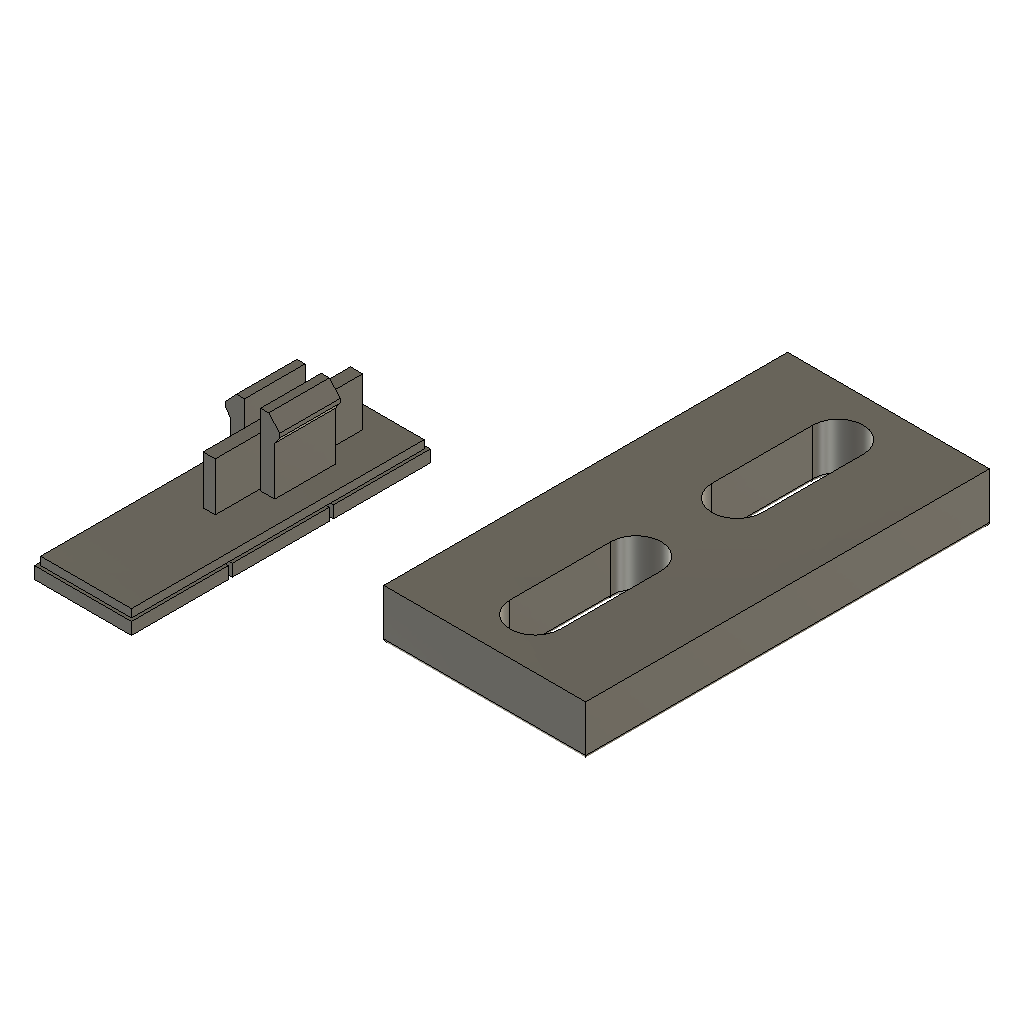
axial-mosaic-tile-bottom-terminal (Autodesk Fusion 360 design; units mm, degrees)
part number: 2026-10-31-10-05-46-988
part number: 2026-10-31-10-05-47-305
part number: 2026-10-31-10-05-48-139
part number: 2026-10-31-10-05-48-389
part number: 2026-10-31-10-05-48-679
part number: 2026-10-31-10-05-48-982
Autodesk Fusion 360 part; units mm, degrees
ref_plane "WorkPlane1" through (0, 0, -0.8) normal (0, 0, 1) x (1, 0, 0) in component "PRINT tile core"
sketch "Structural backing with terminal extension sketch" plane through (0, 0, -0.8) normal (0, 0, 1) x (1, 0, 0) in component "PRINT tile core"
  line L0 (-4.5, -19.5) -> (4.5, -19.5)
  line L1 (4.5, -19.5) -> (4.5, 9.5)
  line L2 (4.5, 9.5) -> (-4.5, 9.5)
  line L3 (-4.5, 9.5) -> (-4.5, -19.5)
  dimension "d73" = 4.5
  dimension "d74" = 19.5
  dimension "d75" = 9
  dimension "d76" = 29
  constraint horizontal L0
  constraint vertical L1
  constraint horizontal L2
  constraint vertical L3
  measures "d73" horizontal distance of origin L0.start
  measures "d74" vertical distance of origin L0.start
  measures "d75" horizontal distance of L0.start L0.end
  measures "d76" vertical distance of L0.end L1.end
extrude "Structural backing with terminal extension" add sketch "Structural backing with terminal extension sketch" along normal blind 0.8 makes body 1 in component "PRINT tile core"
sketch "Central gravity bearing and vertical registration spine sketch" plane through (0, 0, 0) normal (0, 0, 1) x (1, 0, 0) in component "PRINT tile core"
  line L0 (-0.6, -7.3) -> (0.6, -7.3)
  line L1 (0.6, -7.3) -> (0.6, 7.3)
  line L2 (0.6, 7.3) -> (-0.6, 7.3)
  line L3 (-0.6, 7.3) -> (-0.6, -7.3)
  dimension "d79" = 0.6
  dimension "d80" = 7.3
  dimension "d81" = 1.2
  dimension "d82" = 14.6
  constraint horizontal L0
  constraint vertical L1
  constraint horizontal L2
  constraint vertical L3
  measures "d79" horizontal distance of origin L0.start
  measures "d80" vertical distance of origin L0.start
  measures "d81" horizontal distance of L0.start L0.end
  measures "d82" vertical distance of L0.end L1.end
extrude "Central gravity bearing and vertical registration spine" add sketch "Central gravity bearing and vertical registration spine sketch" along normal blind 4.8 bodies 1 in component "PRINT tile core"
ref_plane "WorkPlane2" through (0, -3, 0) normal (0, 1, 0) x (0, 0, 1) in component "PRINT tile core"
sketch "Axial spring -1 with insertion and release ramps sketch" plane through (0, -3, 0) normal (0, 1, 0) x (1, 0, 0) in component "PRINT tile core"
  line L0 (-0.8, 0) -> (-2.2, 0)
  line L1 (-2.2, 0) -> (-2.2, -4.8)
  line L2 (-2.2, -4.8) -> (-2.7, -5.5)
  line L3 (-2.7, -5.5) -> (-2.7, -5.9)
  line L4 (-2.7, -5.9) -> (-1.6, -7.1)
  line L5 (-1.6, -7.1) -> (-0.8, -7.1)
  line L6 (-0.8, -7.1) -> (-0.8, 0)
  dimension "d87" = 0.8
  dimension "d88" = 2.2
  dimension "d89" = 4.8
  dimension "d90" = 2.7
  dimension "d91" = 5.5
  dimension "d92" = 5.9
  dimension "d93" = 1.6
  dimension "d94" = 7.1
  constraint horizontal origin L0.start
  constraint horizontal L0.start L0.end
  constraint vertical L0.end L1.end
  constraint vertical L2.end L3.end
  constraint vertical L0.start L5.end
  constraint horizontal L4.end L5.end
  measures "d87" horizontal distance of origin L0.start
  measures "d88" horizontal distance of origin L0.end
  measures "d89" vertical distance of origin L1.end
  measures "d90" horizontal distance of origin L2.end
  measures "d91" vertical distance of origin L2.end
  measures "d92" vertical distance of origin L3.end
  measures "d93" horizontal distance of origin L4.end
  measures "d94" vertical distance of origin L4.end
extrude "Axial spring -1 with insertion and release ramps" add sketch "Axial spring -1 with insertion and release ramps sketch" along normal blind 6 bodies 1 in component "PRINT tile core"
ref_plane "WorkPlane3" through (0, -3, 0) normal (0, 1, 0) x (0, 0, 1) in component "PRINT tile core"
sketch "Axial spring 1 with insertion and release ramps sketch" plane through (0, -3, 0) normal (0, 1, 0) x (1, 0, 0) in component "PRINT tile core"
  line L0 (0.8, 0) -> (2.2, 0)
  line L1 (2.2, 0) -> (2.2, -4.8)
  line L2 (2.2, -4.8) -> (2.7, -5.5)
  line L3 (2.7, -5.5) -> (2.7, -5.9)
  line L4 (2.7, -5.9) -> (1.6, -7.1)
  line L5 (1.6, -7.1) -> (0.8, -7.1)
  line L6 (0.8, -7.1) -> (0.8, 0)
  dimension "d99" = 0.8
  dimension "d100" = 2.2
  dimension "d101" = 4.8
  dimension "d102" = 2.7
  dimension "d103" = 5.5
  dimension "d104" = 5.9
  dimension "d105" = 1.6
  dimension "d106" = 7.1
  constraint horizontal origin L0.start
  constraint horizontal L0.start L0.end
  constraint vertical L0.end L1.end
  constraint vertical L2.end L3.end
  constraint vertical L0.start L5.end
  constraint horizontal L4.end L5.end
  measures "d99" horizontal distance of origin L0.start
  measures "d100" horizontal distance of origin L0.end
  measures "d101" vertical distance of origin L1.end
  measures "d102" horizontal distance of origin L2.end
  measures "d103" vertical distance of origin L2.end
  measures "d104" vertical distance of origin L3.end
  measures "d105" horizontal distance of origin L4.end
  measures "d106" vertical distance of origin L4.end
extrude "Axial spring 1 with insertion and release ramps" add sketch "Axial spring 1 with insertion and release ramps sketch" along normal blind 6 bodies 1 in component "PRINT tile core"
ref_plane "WorkPlane1" through (0, 0, -2) normal (0, 0, 1) x (1, 0, 0) in component "COLOR pixel lower"
sketch "Co-printed pixel color region sketch" plane through (0, 0, -2) normal (0, 0, 1) x (1, 0, 0) in component "COLOR pixel lower"
  line L0 (-4.8, -9.8) -> (4.8, -9.8)
  line L1 (4.8, -9.8) -> (4.8, -0.2)
  line L2 (4.8, -0.2) -> (-4.8, -0.2)
  line L3 (-4.8, -0.2) -> (-4.8, -9.8)
  dimension "d111" = 4.8
  dimension "d112" = 9.8
  dimension "d113" = 9.6
  dimension "d114" = 9.6
  constraint horizontal L0
  constraint vertical L1
  constraint horizontal L2
  constraint vertical L3
  measures "d111" horizontal distance of origin L0.start
  measures "d112" vertical distance of origin L0.start
  measures "d113" horizontal distance of L0.start L0.end
  measures "d114" vertical distance of L0.end L1.end
extrude "Co-printed pixel color region" add sketch "Co-printed pixel color region sketch" along normal blind 1.2 separate body makes body 2 in component "COLOR pixel lower"
ref_plane "WorkPlane1" through (0, 0, -2) normal (0, 0, 1) x (1, 0, 0) in component "COLOR pixel upper"
sketch "Co-printed pixel color region sketch (2)" plane through (0, 0, -2) normal (0, 0, 1) x (1, 0, 0) in component "COLOR pixel upper"
  line L0 (-4.8, 0.2) -> (4.8, 0.2)
  line L1 (4.8, 0.2) -> (4.8, 9.8)
  line L2 (4.8, 9.8) -> (-4.8, 9.8)
  line L3 (-4.8, 9.8) -> (-4.8, 0.2)
  dimension "d119" = 4.8
  dimension "d120" = 0.2
  dimension "d121" = 9.6
  dimension "d122" = 9.6
  constraint horizontal L0
  constraint vertical L1
  constraint horizontal L2
  constraint vertical L3
  measures "d119" horizontal distance of origin L0.start
  measures "d120" vertical distance of origin L0.start
  measures "d121" horizontal distance of L0.start L0.end
  measures "d122" vertical distance of L0.end L1.end
extrude "Co-printed pixel color region'" add sketch "Co-printed pixel color region sketch (2)" along normal blind 1.2 separate body makes body 3 in component "COLOR pixel upper"
ref_plane "WorkPlane1" through (0, 0, -2) normal (0, 0, 1) x (1, 0, 0) in component "COLOR pixel terminal"
sketch "Co-printed pixel color region sketch (3)" plane through (0, 0, -2) normal (0, 0, 1) x (1, 0, 0) in component "COLOR pixel terminal"
  line L0 (-4.8, -19.8) -> (4.8, -19.8)
  line L1 (4.8, -19.8) -> (4.8, -10.2)
  line L2 (4.8, -10.2) -> (-4.8, -10.2)
  line L3 (-4.8, -10.2) -> (-4.8, -19.8)
  dimension "d127" = 4.8
  dimension "d128" = 19.8
  dimension "d129" = 9.6
  dimension "d130" = 9.6
  constraint horizontal L0
  constraint vertical L1
  constraint horizontal L2
  constraint vertical L3
  measures "d127" horizontal distance of origin L0.start
  measures "d128" vertical distance of origin L0.start
  measures "d129" horizontal distance of L0.start L0.end
  measures "d130" vertical distance of L0.end L1.end
extrude "Co-printed pixel color region''" add sketch "Co-printed pixel color region sketch (3)" along normal blind 1.2 separate body makes body 4 in component "COLOR pixel terminal"
sketch "Coupon blank sketch" plane through (0, 0, 0) normal (0, 0, 1) x (1, 0, 0) in component "PRINT fit coupon"
  line L0 (20, -10) -> (40, -10)
  line L1 (40, -10) -> (40, 30)
  line L2 (40, 30) -> (20, 30)
  line L3 (20, 30) -> (20, -10)
  dimension "d133" = 20
  dimension "d134" = 10
  dimension "d135" = 20
  dimension "d136" = 40
  constraint horizontal L0
  constraint vertical L1
  constraint horizontal L2
  constraint vertical L3
  measures "d133" horizontal distance of origin L0.start
  measures "d134" vertical distance of origin L0.start
  measures "d135" horizontal distance of L0.start L0.end
  measures "d136" vertical distance of L0.end L1.end
extrude "Coupon blank" add sketch "Coupon blank sketch" along normal blind 5 separate body makes body 5 in component "PRINT fit coupon"
sketch "Standard throat test slots constrained seed" plane through (0, 0, 0) normal (0, 0, 1) x (1, 0, 0) in component "PRINT fit coupon"
  line L0 (32.5, -5) -> (32.5, 5)
  arc A0 (32.5, 5) -> (27.5, 5) centre (30, 5) ccw
  line L1 (27.5, 5) -> (27.5, -5)
  arc A1 (27.5, -5) -> (32.5, -5) centre (30, -5) ccw
  line L2 (30, -5) -> (30, 5) construction
  line L3 (30, -5) -> (40, -5) construction
  dimension "d139" = 5
  dimension "d140" = 10
  dimension "d141" = 90
  dimension "d142" = 10
  dimension "d143" = 30
  dimension "d144" = 5
  constraint tangent L0 A0
  constraint tangent A0 L1
  constraint tangent L1 A1
  constraint tangent L0 A1
  constraint parallel L0 L1
  constraint horizontal L3
  measures "d139" diameter of A0
  measures "d140" distance of A1.centre A0.centre
  measures "d141" angle of L2 L3
  measures "d142" horizontal distance of A1.centre L3.end
  measures "d143" horizontal distance of origin A1.centre
  measures "d144" vertical distance of origin A1.centre
extrude "Standard throat test slots through cut" cut sketch "Standard throat test slots constrained seed" along normal blind 5 bodies 5 in component "PRINT fit coupon"
pattern_linear "Standard throat test slots lattice" count 1 spacing 20 along (1, 0, 0) count 2 spacing 20 along (0, 1, 0) of "Standard throat test slots through cut" in component "PRINT fit coupon"
fillet "Rounded coupon entrances" radius 0.4 2 faces at (22.5093, 8.4575, 0) (22.5093, 8.4575, 0) on bodies 5 in component "PRINT fit coupon"
component "PRINT tile core" placed x (1, 0, 0) y (0, 1, 0) z (0, 0, 1) at (0, 0, 0)
component "COLOR pixel lower" placed x (1, 0, 0) y (0, 1, 0) z (0, 0, 1) at (0, 0, 0)
component "COLOR pixel upper" placed x (1, 0, 0) y (0, 1, 0) z (0, 0, 1) at (0, 0, 0)
component "COLOR pixel terminal" placed x (1, 0, 0) y (0, 1, 0) z (0, 0, 1) at (0, 0, 0)
component "PRINT fit coupon" placed x (1, 0, 0) y (0, 1, 0) z (0, 0, 1) at (0, 0, 0)
equation "columns = 12" comment "Even integer 4..14; each cell is 20 mm"
equation "rows = 12" comment "Even integer 4..14"
equation "pitch = 20 mm" comment "Keep for dense SKADIS compatible lattice"
equation "panelWidth = columns * pitch" comment "Nominal module pitch X"
equation "panelHeight = rows * pitch" comment "Nominal module pitch Y"
equation "seamGap = 0.35 mm" comment "Physical envelope shrinks around fixed lattice"
equation "boardThickness = 5 mm" comment "Fit-test with real hooks"
equation "slotWidth = 5 mm" comment "Minimum throat width"
equation "slotHeight = 15 mm" comment "Minimum throat height"
equation "entryRadius = 0.4 mm" comment "Front slot and perimeter edge rounding"
equation "cornerRadius = 6 mm" comment "Plan-view panel corner rounding"
equation "hookClearance = 10 mm" comment "PROVISIONAL unobstructed depth behind board; carriers begin at its rear boundary"
equation "frameZ = carrierZ + carrierThickness" comment "Front extrusion datum"
equation "profileMouth = 6.28 mm" comment "User measured mouth"
equation "profileCavity = 11 mm" comment "User measured widest cavity"
equation "profileDepth = 6.2 mm" comment "User measured face-to-floor depth"
equation "profileFloor = 5.7 mm" comment "User estimate, lower confidence"
equation "profileLip = 1.5 mm" comment "Unmeasured; tentative comparable catalog value"
equation "profileTaperStart = profileDepth - ( profileCavity - profileFloor ) / 2" comment "Assumed 45-degree inner slopes"
equation "profileBore = 5 mm" comment "Unmeasured central bore, reference only"
equation "nutWidth = 8.8 mm" comment "Provisional low-profile METAL T-nut envelope, not old rectangular carrier"
equation "nutLength = 12 mm" comment "End-loaded anti-rotation metal nut envelope"
equation "nutThickness = 2.7 mm" comment "Thin nut reference; fit/load still unverified"
equation "jointLeg = 18 mm" comment "In-bay angle footprint"
equation "jointThickness = 3 mm" comment "Metal bracket thickness"
equation "jointDepth = 16 mm" comment "Bracket depth within 20 mm rail"
equation "sideScrewLength = 8 mm" comment "M5x8 reference; check against actual bracket and nut"
equation "wallTabHeight = 24 mm" comment "Tab along extrusion"
equation "wallTabReach = 22 mm" comment "Tab into open bay"
equation "wallAnchorClearance = 6.5 mm" comment "Placeholder wall anchor interface"
equation "wallDriverDiameter = 12 mm" comment "Clear tool envelope in open bays"
equation "keyDriverDiameter = 5 mm" comment "Short hex-key working-leg envelope"
equation "keyDriverReach = 20 mm" comment "Short hex-key working-leg reach"
equation "supportWidth = 3.2 mm" comment "Prototype blade; two perimeter lines need print review"
equation "supportLength = 12 mm" comment "Compression bearing length"
equation "hookEnvelopeWidth = 6 mm" comment "Conservative provisional continuous hook column"
equation "carrierThickness = 7 mm" comment "Room for captive M2 nut and stock M5x12"
equation "panelClearance = 2.4 mm" comment "M2 clearance"
equation "panelHeadPocket = 4 mm" comment "DIN965 3.8 mm head plus 0.1 mm recess"
equation "carrierHeadPocket = 9.4 mm" comment "DIN965 M5 9.2 mm head plus recess"
equation "carrierBore = 5.5 mm" comment "M5 clearance"
equation "tongueWidth = 2.8 mm" comment "Rear axial registration tongue"
equation "tongueLength = 8 mm" comment "Axial release registration"
equation "tongueDepth = 0.6 mm" comment "Tongue engagement"
equation "registerClearance = 0.2 mm" comment "Each side of printed tongue"
equation "carrierZ = boardThickness + hookClearance" comment "Rear hook cavity boundary"
equation "stepCorner = 0.6 mm" comment "Small plan corner relief; printed fit remains untested"
equation "pixelGap = 0.4 mm" comment "Prototype; tune after physical testing"
equation "pixelThickness = 1.2 mm" comment "Prototype; tune after physical testing"
equation "tileBack = 0.8 mm" comment "Prototype; tune after physical testing"
equation "snapInterference = 0.4 mm" comment "Prototype; tune after physical testing"
equation "d71 = -tileBack"
equation "d73 = abs(-4.5 mm)"
equation "d74 = abs(-19.5 mm)"
equation "d77 = tileBack"
equation "d79 = abs(-0.6 mm)"
equation "d80 = abs(-slotHeight / 2 + 0.2 mm)"
equation "d82 = slotHeight - 0.4 mm"
equation "d83 = boardThickness - 0.2 mm"
equation "d85 = ( -3 mm ) * 1.0"
equation "d87 = abs(( ( 0.8 mm ) * -1 ) * 1)"
equation "d88 = abs(( ( 2.2 mm ) * -1 ) * 1)"
equation "d89 = abs(( boardThickness - 0.2 mm ) * -1)"
equation "d90 = abs(( ( ( slotWidth + snapInterference ) / 2 ) * -1 ) * 1)"
equation "d91 = abs(( boardThickness + 0.5 mm ) * -1)"
equation "d92 = abs(( boardThickness + 0.9 mm ) * -1)"
equation "d93 = abs(( ( 1.6 mm ) * -1 ) * 1)"
equation "d94 = abs(( boardThickness + 2.1 mm ) * -1)"
equation "d95 = ( 6 mm ) * 1.0"
equation "d97 = ( -3 mm ) * 1.0"
equation "d99 = abs(( ( 0.8 mm ) * 1 ) * 1)"
equation "d100 = abs(( ( 2.2 mm ) * 1 ) * 1)"
equation "d101 = abs(( boardThickness - 0.2 mm ) * -1)"
equation "d102 = abs(( ( ( slotWidth + snapInterference ) / 2 ) * 1 ) * 1)"
equation "d103 = abs(( boardThickness + 0.5 mm ) * -1)"
equation "d104 = abs(( boardThickness + 0.9 mm ) * -1)"
equation "d105 = abs(( ( 1.6 mm ) * 1 ) * 1)"
equation "d106 = abs(( boardThickness + 2.1 mm ) * -1)"
equation "d107 = ( 6 mm ) * 1.0"
equation "d109 = -tileBack - pixelThickness"
equation "d111 = abs(-5 mm + pixelGap / 2)"
equation "d112 = abs(-10 mm + pixelGap / 2)"
equation "d113 = 10 mm - pixelGap"
equation "d114 = 10 mm - pixelGap"
equation "d115 = pixelThickness"
equation "d117 = -tileBack - pixelThickness"
equation "d119 = abs(-5 mm + pixelGap / 2)"
equation "d120 = abs(pixelGap / 2)"
equation "d121 = 10 mm - pixelGap"
equation "d122 = 10 mm - pixelGap"
equation "d123 = pixelThickness"
equation "d125 = -tileBack - pixelThickness"
equation "d127 = abs(-5 mm + pixelGap / 2)"
equation "d128 = abs(-20 mm + pixelGap / 2)"
equation "d129 = 10 mm - pixelGap"
equation "d130 = 10 mm - pixelGap"
equation "d131 = pixelThickness"
equation "d133 = abs(20 mm)"
equation "d134 = abs(-10 mm)"
equation "d137 = boardThickness"
equation "d139 = slotWidth"
equation "d140 = slotHeight - slotWidth"
equation "d142 = pitch / 2"
equation "d143 = abs(30 mm)"
equation "d144 = abs(( 0 mm ) - ( slotHeight - slotWidth ) / 2)"
equation "d145 = boardThickness"
equation "d149 = pitch"
equation "d150 = pitch"
equation "d152 = entryRadius"
